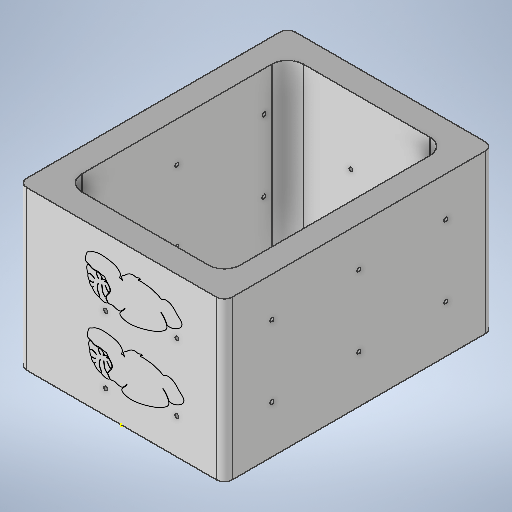
# Autodesk Inventor part: Brain Embedding Chamber 2
Saved by Autodesk Inventor 2025.2 (Build 292293000, 293)
## iProperties
Created: 2020-11-17
Part Number: Brain Embedding Chamber 2
Material: Generic
Document SubType Name: Modeling
Designer: stownsend
Density: 1 g/cm^3
Appearance: Default
Mass: 6.51972 g
Surface Area: 49.5654 cm^2
Volume: 6.51972 cm^3
Author: stownsend
Autodesk Inventor part; units mm, degrees
(part 1 of 2)
ref_plane "YZ Plane" through (0, 0, 0) normal (1, 0, 0) x (0, 1, 0)
ref_plane "XZ Plane" through (0, 0, 0) normal (0, 1, 0) x (-1, 0, 0)
ref_plane "XY Plane" through (0, 0, 0) normal (0, 0, 1) x (1, 0, 0)
sketch "Sketch1" plane through (0, 0, 0) normal (0, 0, 1) x (1, 0, 0)
  line L0 (17, -13) -> (-17, -13)
  line L1 (-17, -13) -> (-17, 13)
  line L2 (-17, 13) -> (17, 13)
  line L3 (17, 13) -> (17, -13)
  line L4 (14, 10) -> (-14, 10)
  line L5 (-14, 10) -> (-14, -10)
  line L6 (-14, -10) -> (14, -10)
  line L7 (14, -10) -> (14, 10)
  point P0 (0, 0)
  dimension "d132" = 26
  dimension "d133" = 34
  dimension "d134" = 17
  dimension "d135" = 13
  dimension "d136" = 20
  dimension "d140" = 28
  dimension "d141" = 14
  dimension "d142" = 10
  constraints: 16 end point, 4 parallel, 2 perpendicular, 1 horizontal, 1 horizontal alignment
  measures "d132" distance between parallel lines of L0 L2
  measures "d133" distance between parallel lines of L1 L3
  measures "d134" distance from line of L3 point (0, 0)
  measures "d135" distance from line of L2 point (0, 0)
  measures "d136" distance between parallel lines of L6 L4
  measures "d140" distance between parallel lines of L5 L7
  measures "d141" distance from line of L7 point (0, 0)
  measures "d142" distance from line of L4 point (0, 0)
extrude "Extrusion1" add sketch "Sketch1" along normal blind 20
sketch "Sketch2" plane through (-14, 0, 0) normal (0, -1, 0) x (1, 0, 0)
  circle A0 centre (3, 15) radius 0.25
  line L0 (31, 20) -> (-3, 20) projected
  circle A1 centre (14, 15) radius 0.25
  circle A2 centre (25, 15) radius 0.25
  circle A3 centre (3, 6) radius 0.25
  circle A4 centre (14, 6) radius 0.25
  circle A5 centre (25, 6) radius 0.25
  point P0 (14, 0)
  point P1 (29, 20)
  dimension "d8" = 0.5
  dimension "d15" = 0.5
  dimension "d18" = 0.5
  dimension "d19" = 0.5
  dimension "d63" = 5
  dimension "d66" = 9
  dimension "d67" = 11
  dimension "d68" = 11
  dimension "d69" = 0.5
  dimension "d70" = 0.5
  constraints: 6 centre point, 4 horizontal alignment, 4 vertical alignment
  measures "d8" diameter of A0
  measures "d15" diameter of A3
  measures "d18" diameter of A4
  measures "d19" diameter of A5
  measures "d63" distance from line of A1.centre L0
  measures "d66" distance of A4.centre A1.centre
  measures "d67" distance of A0.centre A1.centre
  measures "d68" distance of A2.centre A1.centre
  measures "d69" diameter of A1
  measures "d70" diameter of A2
extrude "Extrusion2" cut sketch "Sketch2" along normal through all both and the other way through all
sketch "Sketch3" plane through (0, -12, 0) normal (1, 0, 0) x (0, 0, -1)
  circle A0 centre (-13, 5) radius 0.25
  circle A1 centre (-11.5, 14) radius 0.25
  circle A2 centre (-4.5, 5) radius 0.25
  circle A3 centre (-3, 14) radius 0.25
  point P0 (-20, -1)
  point P1 (0, 12)
  dimension "d28" = 0.5
  dimension "d29" = 0.5
  dimension "d30" = 0.5
  dimension "d31" = 0.5
  dimension "d167" = 7
  dimension "d168" = 2
  dimension "d169" = 9
  constraints: 4 centre point, 2 horizontal alignment
  measures "d28" diameter of A0
  measures "d29" diameter of A1
  measures "d30" diameter of A2
  measures "d31" diameter of A3
  measures "d167" vertical distance of point (0, 12) A2.centre
  measures "d168" vertical distance of point (0, 12) A3.centre
  measures "d169" vertical distance of A3.centre A2.centre
extrude "Extrusion3" cut sketch "Sketch3" along normal through all both and the other way through all
fillet "Fillet1" radius 1 4 edges at (-17, 13, 10) (17, 13, 10) (17, -13, 10) (-17, -13, 10)
fillet "Fillet2" radius 2 4 edges at (-14, 10, 10) (14, 10, 10) (14, -10, 10) (-14, -10, 10)
sketch "Sketch8" plane through (-17, -12, 0) normal (-1, 0, 0) x (0, 0, 1)
  spline S0 degree 3 poles (14.8061, 7.0077) (14.8126, 6.9913) (14.813, 7.0034) (14.8073, 6.9818) knots 0 0 0 0 0.017241 0.017241 0.017241 0.017241
  line L0 (14.8061, 7.0077) -> (14.8126, 6.9913) construction
  line L1 (14.8126, 6.9913) -> (14.813, 7.0034) construction
  line L2 (14.813, 7.0034) -> (14.8073, 6.9818) construction
  line L3 (14.8073, 6.9818) -> (14.7531, 6.8993)
  spline S1 degree 3 poles (14.7531, 6.8993) (14.7531, 6.8993) (14.7198, 6.8577) (14.689, 6.8235) (14.6576, 6.7884) knots 0.034483 0.034483 0.034483 0.034483 0.034483 0.051724 0.051724 0.051724 0.051724
  line L4 (14.7531, 6.8993) -> (14.7198, 6.8577) construction
  line L5 (14.7198, 6.8577) -> (14.689, 6.8235) construction
  line L6 (14.689, 6.8235) -> (14.6576, 6.7884) construction
  spline S2 degree 3 poles (14.6576, 6.7884) (14.6574, 6.7883) (14.497, 6.6092) (14.1688, 6.4006) (13.9416, 6.2976) knots 0.051724 0.051724 0.051724 0.051724 0.051724 0.068966 0.068966 0.068966 0.068966
  line L7 (14.6576, 6.7884) -> (14.497, 6.6092) construction
  line L8 (14.497, 6.6092) -> (14.1688, 6.4006) construction
  line L9 (14.1688, 6.4006) -> (13.9416, 6.2976) construction
  spline S3 degree 3 poles (13.9416, 6.2976) (13.9415, 6.2975) (13.8045, 6.2354) (13.8065, 6.2363) (13.7719, 6.0706) knots 0.068966 0.068966 0.068966 0.068966 0.068966 0.086207 0.086207 0.086207 0.086207
  line L10 (13.9416, 6.2976) -> (13.8045, 6.2354) construction
  line L11 (13.8045, 6.2354) -> (13.8065, 6.2363) construction
  line L12 (13.8065, 6.2363) -> (13.7719, 6.0706) construction
  spline S4 degree 3 poles (13.7719, 6.0706) (13.7719, 6.0705) (13.7476, 5.9537) (13.7493, 5.821) (13.7696, 5.7021) knots 0.086207 0.086207 0.086207 0.086207 0.086207 0.103448 0.103448 0.103448 0.103448
  line L13 (13.7719, 6.0706) -> (13.7476, 5.9537) construction
  line L14 (13.7476, 5.9537) -> (13.7493, 5.821) construction
  line L15 (13.7493, 5.821) -> (13.7696, 5.7021) construction
  spline S5 degree 3 poles (13.7696, 5.7021) (13.7696, 5.7016) (13.8519, 5.2201) (14.3169, 4.3306) (14.8371, 4.3531) knots 0.103448 0.103448 0.103448 0.103448 0.103448 0.12069 0.12069 0.12069 0.12069
  line L16 (13.7696, 5.7021) -> (13.8519, 5.2201) construction
  line L17 (13.8519, 5.2201) -> (14.3169, 4.3306) construction
  line L18 (14.3169, 4.3306) -> (14.8371, 4.3531) construction
  spline S6 degree 3 poles (14.8371, 4.3531) (14.8374, 4.3531) (15.1353, 4.366) (15.3904, 4.7704) (15.6148, 4.9893) knots 0.12069 0.12069 0.12069 0.12069 0.12069 0.137931 0.137931 0.137931 0.137931
  line L19 (14.8371, 4.3531) -> (15.1353, 4.366) construction
  line L20 (15.1353, 4.366) -> (15.3904, 4.7704) construction
  line L21 (15.3904, 4.7704) -> (15.6148, 4.9893) construction
  spline S7 degree 3 poles (15.6148, 4.9893) (15.615, 4.9895) (15.7957, 5.1659) (15.8747, 5.1722) (16.1278, 5.4768) knots 0.137931 0.137931 0.137931 0.137931 0.137931 0.155172 0.155172 0.155172 0.155172
  line L22 (15.6148, 4.9893) -> (15.7957, 5.1659) construction
  line L23 (15.7957, 5.1659) -> (15.8747, 5.1722) construction
  line L24 (15.8747, 5.1722) -> (16.1278, 5.4768) construction
  spline S8 degree 3 poles (16.1278, 5.4768) (16.1279, 5.4769) (16.2353, 5.6061) (16.3693, 5.7817) (16.4219, 5.9929) knots 0.155172 0.155172 0.155172 0.155172 0.155172 0.172414 0.172414 0.172414 0.172414
  line L25 (16.1278, 5.4768) -> (16.2353, 5.6061) construction
  line L26 (16.2353, 5.6061) -> (16.3693, 5.7817) construction
  line L27 (16.3693, 5.7817) -> (16.4219, 5.9929) construction
  spline S9 degree 3 poles (16.4219, 5.9929) (16.422, 5.9936) (16.5964, 6.6941) (16.314, 6.742) (16.2973, 6.9436) knots 0.172414 0.172414 0.172414 0.172414 0.172414 0.189655 0.189655 0.189655 0.189655
  line L28 (16.4219, 5.9929) -> (16.5964, 6.6941) construction
  line L29 (16.5964, 6.6941) -> (16.314, 6.742) construction
  line L30 (16.314, 6.742) -> (16.2973, 6.9436) construction
  spline S10 degree 3 poles (16.2973, 6.9436) (16.2973, 6.9437) (16.2877, 7.0581) (16.3807, 7.1531) (16.4264, 7.2259) knots 0.189655 0.189655 0.189655 0.189655 0.189655 0.206897 0.206897 0.206897 0.206897
  line L31 (16.2973, 6.9436) -> (16.2877, 7.0581) construction
  line L32 (16.2877, 7.0581) -> (16.3807, 7.1531) construction
  line L33 (16.3807, 7.1531) -> (16.4264, 7.2259) construction
  spline S11 degree 3 poles (16.4264, 7.2259) (16.4265, 7.2261) (16.5667, 7.4493) (16.5591, 7.5412) (16.6453, 7.8009) knots 0.206897 0.206897 0.206897 0.206897 0.206897 0.224138 0.224138 0.224138 0.224138
  line L34 (16.4264, 7.2259) -> (16.5667, 7.4493) construction
  line L35 (16.5667, 7.4493) -> (16.5591, 7.5412) construction
  line L36 (16.5591, 7.5412) -> (16.6453, 7.8009) construction
  spline S12 degree 3 poles (16.6453, 7.8009) (16.6454, 7.8012) (16.7199, 8.0256) (16.7906, 8.1594) (16.8362, 8.4188) knots 0.224138 0.224138 0.224138 0.224138 0.224138 0.241379 0.241379 0.241379 0.241379
  line L37 (16.6453, 7.8009) -> (16.7199, 8.0256) construction
  line L38 (16.7199, 8.0256) -> (16.7906, 8.1594) construction
  line L39 (16.7906, 8.1594) -> (16.8362, 8.4188) construction
  spline S13 degree 3 poles (16.8362, 8.4188) (16.8362, 8.4191) (16.8785, 8.6594) (16.8917, 8.9062) (16.9124, 9.1542) knots 0.241379 0.241379 0.241379 0.241379 0.241379 0.258621 0.258621 0.258621 0.258621
  line L40 (16.8362, 8.4188) -> (16.8785, 8.6594) construction
  line L41 (16.8785, 8.6594) -> (16.8917, 8.9062) construction
  line L42 (16.8917, 8.9062) -> (16.9124, 9.1542) construction
  spline S14 degree 3 poles (16.9124, 9.1542) (16.9124, 9.1543) (16.9224, 9.275) (16.9444, 9.4093) (16.9412, 9.5299) knots 0.258621 0.258621 0.258621 0.258621 0.258621 0.275862 0.275862 0.275862 0.275862
  line L43 (16.9124, 9.1542) -> (16.9224, 9.275) construction
  line L44 (16.9224, 9.275) -> (16.9444, 9.4093) construction
  line L45 (16.9444, 9.4093) -> (16.9412, 9.5299) construction
  spline S15 degree 3 poles (16.9412, 9.5299) (16.9412, 9.53) (16.9385, 9.6335) (16.8885, 9.8259) (16.9091, 9.8972) knots 0.275862 0.275862 0.275862 0.275862 0.275862 0.293103 0.293103 0.293103 0.293103
  line L46 (16.9412, 9.5299) -> (16.9385, 9.6335) construction
  line L47 (16.9385, 9.6335) -> (16.8885, 9.8259) construction
  line L48 (16.8885, 9.8259) -> (16.9091, 9.8972) construction
  spline S16 degree 3 poles (16.9091, 9.8972) (16.9092, 9.8971) (17.0279, 9.8719) (17.0313, 9.724) (17.1389, 9.6266) knots 0.293103 0.293103 0.293103 0.293103 0.293103 0.310345 0.310345 0.310345 0.310345
  line L49 (16.9091, 9.8972) -> (17.0279, 9.8719) construction
  line L50 (17.0279, 9.8719) -> (17.0313, 9.724) construction
  line L51 (17.0313, 9.724) -> (17.1389, 9.6266) construction
  spline S17 degree 3 poles (17.1389, 9.6266) (17.139, 9.6267) (17.2834, 9.6997) (17.1799, 9.8422) (17.1328, 9.9522) knots 0.310345 0.310345 0.310345 0.310345 0.310345 0.327586 0.327586 0.327586 0.327586
  line L52 (17.1389, 9.6266) -> (17.2834, 9.6997) construction
  line L53 (17.2834, 9.6997) -> (17.1799, 9.8422) construction
  line L54 (17.1799, 9.8422) -> (17.1328, 9.9522) construction
  spline S18 degree 3 poles (17.1328, 9.9522) (17.1327, 9.9523) (17.0531, 10.138) (17.091, 10.1943) (17.1335, 10.3764) knots 0.327586 0.327586 0.327586 0.327586 0.327586 0.344828 0.344828 0.344828 0.344828
  line L55 (17.1328, 9.9522) -> (17.0531, 10.138) construction
  line L56 (17.0531, 10.138) -> (17.091, 10.1943) construction
  line L57 (17.091, 10.1943) -> (17.1335, 10.3764) construction
  spline S19 degree 3 poles (17.1335, 10.3764) (17.1336, 10.3768) (17.2249, 10.7687) (16.9931, 11.1829) (16.7277, 11.4526) knots 0.344828 0.344828 0.344828 0.344828 0.344828 0.362069 0.362069 0.362069 0.362069
  line L58 (17.1335, 10.3764) -> (17.2249, 10.7687) construction
  line L59 (17.2249, 10.7687) -> (16.9931, 11.1829) construction
  line L60 (16.9931, 11.1829) -> (16.7277, 11.4526) construction
  spline S20 degree 3 poles (16.7277, 11.4526) (16.7276, 11.4528) (16.6041, 11.5783) (16.5961, 11.5866) (16.5019, 11.7347) knots 0.362069 0.362069 0.362069 0.362069 0.362069 0.37931 0.37931 0.37931 0.37931
  line L61 (16.7277, 11.4526) -> (16.6041, 11.5783) construction
  line L62 (16.6041, 11.5783) -> (16.5961, 11.5866) construction
  line L63 (16.5961, 11.5866) -> (16.5019, 11.7347) construction
  spline S21 degree 3 poles (16.5019, 11.7347) (16.5017, 11.7351) (16.2722, 12.0958) (16.2178, 11.9762) (15.8447, 11.8717) knots 0.37931 0.37931 0.37931 0.37931 0.37931 0.396552 0.396552 0.396552 0.396552
  line L64 (16.5019, 11.7347) -> (16.2722, 12.0958) construction
  line L65 (16.2722, 12.0958) -> (16.2178, 11.9762) construction
  line L66 (16.2178, 11.9762) -> (15.8447, 11.8717) construction
  spline S22 degree 3 poles (15.8447, 11.8717) (15.8447, 11.8717) (15.8613, 11.8841) (15.9767, 12.0055) (15.9897, 12.0289) knots 0.396552 0.396552 0.396552 0.396552 0.396552 0.413793 0.413793 0.413793 0.413793
  line L67 (15.8447, 11.8717) -> (15.8613, 11.8841) construction
  line L68 (15.8613, 11.8841) -> (15.9767, 12.0055) construction
  line L69 (15.9767, 12.0055) -> (15.9897, 12.0289) construction
  spline S23 degree 3 poles (15.9897, 12.0289) (15.9897, 12.029) (16.0358, 12.1116) (15.9868, 12.1947) (15.9691, 12.2712) knots 0.413793 0.413793 0.413793 0.413793 0.413793 0.431034 0.431034 0.431034 0.431034
  line L70 (15.9897, 12.0289) -> (16.0358, 12.1116) construction
  line L71 (16.0358, 12.1116) -> (15.9868, 12.1947) construction
  line L72 (15.9868, 12.1947) -> (15.9691, 12.2712) construction
  spline S24 degree 3 poles (15.9691, 12.2712) (15.9694, 12.271) (16.298, 12.106) (16.521, 12.0677) (16.7612, 12.3366) knots 0.431034 0.431034 0.431034 0.431034 0.431034 0.448276 0.448276 0.448276 0.448276
  line L73 (15.9691, 12.2712) -> (16.298, 12.106) construction
  line L74 (16.298, 12.106) -> (16.521, 12.0677) construction
  line L75 (16.521, 12.0677) -> (16.7612, 12.3366) construction
  spline S25 degree 3 poles (16.7612, 12.3366) (16.7614, 12.3368) (16.9635, 12.5631) (17.0591, 12.6843) (17.1585, 13.067) knots 0.448276 0.448276 0.448276 0.448276 0.448276 0.465517 0.465517 0.465517 0.465517
  line L76 (16.7612, 12.3366) -> (16.9635, 12.5631) construction
  line L77 (16.9635, 12.5631) -> (17.0591, 12.6843) construction
  line L78 (17.0591, 12.6843) -> (17.1585, 13.067) construction
  spline S26 degree 3 poles (17.1585, 13.067) (17.1587, 13.0675) (17.2966, 13.5982) (17.4342, 14.5011) (17.3195, 15.0596) knots 0.465517 0.465517 0.465517 0.465517 0.465517 0.482759 0.482759 0.482759 0.482759
  line L79 (17.1585, 13.067) -> (17.2966, 13.5982) construction
  line L80 (17.2966, 13.5982) -> (17.4342, 14.5011) construction
  line L81 (17.4342, 14.5011) -> (17.3195, 15.0596) construction
  spline S27 degree 3 poles (17.3195, 15.0596) (17.3193, 15.0604) (17.1617, 15.8281) (17.1237, 15.5942) (16.8389, 16.2465) knots 0.482759 0.482759 0.482759 0.482759 0.482759 0.5 0.5 0.5 0.5
  line L82 (17.3195, 15.0596) -> (17.1617, 15.8281) construction
  line L83 (17.1617, 15.8281) -> (17.1237, 15.5942) construction
  line L84 (17.1237, 15.5942) -> (16.8389, 16.2465) construction
  spline S28 degree 3 poles (16.8389, 16.2465) (16.8388, 16.2467) (16.7576, 16.4327) (16.2269, 16.5214) (16.0324, 16.566) knots 0.5 0.5 0.5 0.5 0.5 0.517241 0.517241 0.517241 0.517241
  line L85 (16.8389, 16.2465) -> (16.7576, 16.4327) construction
  line L86 (16.7576, 16.4327) -> (16.2269, 16.5214) construction
  line L87 (16.2269, 16.5214) -> (16.0324, 16.566) construction
  spline S29 degree 3 poles (16.0324, 16.566) (16.032, 16.5661) (15.596, 16.666) (15.6174, 16.2933) (15.4954, 16.0148) knots 0.517241 0.517241 0.517241 0.517241 0.517241 0.534483 0.534483 0.534483 0.534483
  line L88 (16.0324, 16.566) -> (15.596, 16.666) construction
  line L89 (15.596, 16.666) -> (15.6174, 16.2933) construction
  line L90 (15.6174, 16.2933) -> (15.4954, 16.0148) construction
  spline S30 degree 3 poles (15.4954, 16.0148) (15.4953, 16.0147) (15.4402, 15.8888) (15.3306, 15.7816) (15.3055, 15.635) knots 0.534483 0.534483 0.534483 0.534483 0.534483 0.551724 0.551724 0.551724 0.551724
  line L91 (15.4954, 16.0148) -> (15.4402, 15.8888) construction
  line L92 (15.4402, 15.8888) -> (15.3306, 15.7816) construction
  line L93 (15.3306, 15.7816) -> (15.3055, 15.635) construction
  spline S31 degree 3 poles (15.3055, 15.635) (15.3055, 15.6349) (15.2801, 15.4867) (15.3168, 15.2693) (15.3266, 15.1182) knots 0.551724 0.551724 0.551724 0.551724 0.551724 0.568966 0.568966 0.568966 0.568966
  line L94 (15.3055, 15.635) -> (15.2801, 15.4867) construction
  line L95 (15.2801, 15.4867) -> (15.3168, 15.2693) construction
  line L96 (15.3168, 15.2693) -> (15.3266, 15.1182) construction
  spline S32 degree 3 poles (15.3266, 15.1182) (15.3266, 15.118) (15.3408, 14.8989) (15.2718, 14.8507) (15.226, 14.6656) knots 0.568966 0.568966 0.568966 0.568966 0.568966 0.586207 0.586207 0.586207 0.586207
  line L97 (15.3266, 15.1182) -> (15.3408, 14.8989) construction
  line L98 (15.3408, 14.8989) -> (15.2718, 14.8507) construction
  line L99 (15.2718, 14.8507) -> (15.226, 14.6656) construction
  spline S33 degree 3 poles (15.226, 14.6656) (15.2259, 14.6655) (15.1901, 14.5208) (15.198, 14.2448) (15.1702, 14.1657) knots 0.586207 0.586207 0.586207 0.586207 0.586207 0.603448 0.603448 0.603448 0.603448
  line L100 (15.226, 14.6656) -> (15.1901, 14.5208) construction
  line L101 (15.1901, 14.5208) -> (15.198, 14.2448) construction
  line L102 (15.198, 14.2448) -> (15.1702, 14.1657) construction
  spline S34 degree 3 poles (15.1702, 14.1657) (15.1701, 14.1656) (15.1401, 14.0803) (14.9265, 13.9924) (14.84, 13.9243) knots 0.603448 0.603448 0.603448 0.603448 0.603448 0.62069 0.62069 0.62069 0.62069
  line L103 (15.1702, 14.1657) -> (15.1401, 14.0803) construction
  line L104 (15.1401, 14.0803) -> (14.9265, 13.9924) construction
  line L105 (14.9265, 13.9924) -> (14.84, 13.9243) construction
  spline S35 degree 3 poles (14.84, 13.9243) (14.8398, 13.9241) (14.5692, 13.7109) (14.5143, 13.5521) (14.212, 13.4414) knots 0.62069 0.62069 0.62069 0.62069 0.62069 0.637931 0.637931 0.637931 0.637931
  line L106 (14.84, 13.9243) -> (14.5692, 13.7109) construction
  line L107 (14.5692, 13.7109) -> (14.5143, 13.5521) construction
  line L108 (14.5143, 13.5521) -> (14.212, 13.4414) construction
  spline S36 degree 3 poles (14.212, 13.4414) (14.2116, 13.4412) (13.847, 13.3077) (13.6081, 13.5837) (13.4333, 13.7142) knots 0.637931 0.637931 0.637931 0.637931 0.637931 0.655172 0.655172 0.655172 0.655172
  line L109 (14.212, 13.4414) -> (13.847, 13.3077) construction
  line L110 (13.847, 13.3077) -> (13.6081, 13.5837) construction
  line L111 (13.6081, 13.5837) -> (13.4333, 13.7142) construction
  spline S37 degree 3 poles (13.4333, 13.7142) (13.4329, 13.7145) (13.0095, 14.0307) (12.9457, 13.9631) (12.6948, 13.7991) knots 0.655172 0.655172 0.655172 0.655172 0.655172 0.672414 0.672414 0.672414 0.672414
  line L112 (13.4333, 13.7142) -> (13.0095, 14.0307) construction
  line L113 (13.0095, 14.0307) -> (12.9457, 13.9631) construction
  line L114 (12.9457, 13.9631) -> (12.6948, 13.7991) construction
  spline S38 degree 3 poles (12.6948, 13.7991) (12.6946, 13.799) (12.5373, 13.6961) (12.4745, 13.7226) (12.4908, 13.4539) knots 0.672414 0.672414 0.672414 0.672414 0.672414 0.689655 0.689655 0.689655 0.689655
  line L115 (12.6948, 13.7991) -> (12.5373, 13.6961) construction
  line L116 (12.5373, 13.6961) -> (12.4745, 13.7226) construction
  line L117 (12.4745, 13.7226) -> (12.4908, 13.4539) construction
  spline S39 degree 3 poles (12.4908, 13.4539) (12.4908, 13.4537) (12.5019, 13.2712) (12.5956, 13.174) (12.5115, 12.9833) knots 0.689655 0.689655 0.689655 0.689655 0.689655 0.706897 0.706897 0.706897 0.706897
  line L118 (12.4908, 13.4539) -> (12.5019, 13.2712) construction
  line L119 (12.5019, 13.2712) -> (12.5956, 13.174) construction
  line L120 (12.5956, 13.174) -> (12.5115, 12.9833) construction
  spline S40 degree 3 poles (12.5115, 12.9833) (12.5113, 12.983) (12.3979, 12.7261) (12.2511, 12.3791) (12.4367, 12.0826) knots 0.706897 0.706897 0.706897 0.706897 0.706897 0.724138 0.724138 0.724138 0.724138
  line L121 (12.5115, 12.9833) -> (12.3979, 12.7261) construction
  line L122 (12.3979, 12.7261) -> (12.2511, 12.3791) construction
  line L123 (12.2511, 12.3791) -> (12.4367, 12.0826) construction
  spline S41 degree 3 poles (12.4367, 12.0826) (12.4368, 12.0825) (12.4996, 11.9821) (12.6265, 11.8765) (12.7109, 11.8012) knots 0.724138 0.724138 0.724138 0.724138 0.724138 0.741379 0.741379 0.741379 0.741379
  line L124 (12.4367, 12.0826) -> (12.4996, 11.9821) construction
  line L125 (12.4996, 11.9821) -> (12.6265, 11.8765) construction
  line L126 (12.6265, 11.8765) -> (12.7109, 11.8012) construction
  spline S42 degree 3 poles (12.7109, 11.8012) (12.7109, 11.8012) (12.7532, 11.7635) (12.8205, 11.7124) (12.8733, 11.6779) knots 0.741379 0.741379 0.741379 0.741379 0.741379 0.758621 0.758621 0.758621 0.758621
  line L127 (12.7109, 11.8012) -> (12.7532, 11.7635) construction
  line L128 (12.7532, 11.7635) -> (12.8205, 11.7124) construction
  line L129 (12.8205, 11.7124) -> (12.8733, 11.6779) construction
  spline S43 degree 3 poles (12.8733, 11.6779) (12.8734, 11.6778) (13.0031, 11.5931) (13.0298, 11.6134) (13.0171, 11.557) knots 0.758621 0.758621 0.758621 0.758621 0.758621 0.775862 0.775862 0.775862 0.775862
  line L130 (12.8733, 11.6779) -> (13.0031, 11.5931) construction
  line L131 (13.0031, 11.5931) -> (13.0298, 11.6134) construction
  line L132 (13.0298, 11.6134) -> (13.0171, 11.557) construction
  spline S44 degree 3 poles (13.0171, 11.557) (13.0171, 11.557) (13.014, 11.5564) (13.0055, 11.5565) (13.0075, 11.5566) knots 0.775862 0.775862 0.775862 0.775862 0.775862 0.793103 0.793103 0.793103 0.793103
  line L133 (13.0171, 11.557) -> (13.014, 11.5564) construction
  line L134 (13.014, 11.5564) -> (13.0055, 11.5565) construction
  line L135 (13.0055, 11.5565) -> (13.0075, 11.5566) construction
  line L136 (13.0075, 11.5566) -> (12.9679, 11.5649)
  spline S45 degree 3 poles (12.9679, 11.5649) (12.9676, 11.565) (12.676, 11.6892) (12.365, 12.1397) (12.1726, 12.1992) knots 0.810345 0.810345 0.810345 0.810345 0.810345 0.827586 0.827586 0.827586 0.827586
  line L137 (12.9679, 11.5649) -> (12.676, 11.6892) construction
  line L138 (12.676, 11.6892) -> (12.365, 12.1397) construction
  line L139 (12.365, 12.1397) -> (12.1726, 12.1992) construction
  spline S46 degree 3 poles (12.1726, 12.1992) (12.1723, 12.1994) (11.8022, 12.3138) (11.6485, 11.6062) (11.6148, 11.2762) knots 0.827586 0.827586 0.827586 0.827586 0.827586 0.844828 0.844828 0.844828 0.844828
  line L140 (12.1726, 12.1992) -> (11.8022, 12.3138) construction
  line L141 (11.8022, 12.3138) -> (11.6485, 11.6062) construction
  line L142 (11.6485, 11.6062) -> (11.6148, 11.2762) construction
  spline S47 degree 3 poles (11.6148, 11.2762) (11.6147, 11.2754) (11.5349, 10.4935) (11.8052, 9.4632) (12.0383, 8.7151) knots 0.844828 0.844828 0.844828 0.844828 0.844828 0.862069 0.862069 0.862069 0.862069
  line L143 (11.6148, 11.2762) -> (11.5349, 10.4935) construction
  line L144 (11.5349, 10.4935) -> (11.8052, 9.4632) construction
  line L145 (11.8052, 9.4632) -> (12.0383, 8.7151) construction
  spline S48 degree 3 poles (12.0383, 8.7151) (12.0386, 8.7143) (12.2932, 7.8968) (12.546, 7.2313) (12.9917, 6.6526) knots 0.862069 0.862069 0.862069 0.862069 0.862069 0.87931 0.87931 0.87931 0.87931
  line L146 (12.0383, 8.7151) -> (12.2932, 7.8968) construction
  line L147 (12.2932, 7.8968) -> (12.546, 7.2313) construction
  line L148 (12.546, 7.2313) -> (12.9917, 6.6526) construction
  spline S49 degree 3 poles (12.9917, 6.6526) (12.9919, 6.6523) (13.2189, 6.3577) (13.4659, 6.1033) (13.9717, 6.3634) knots 0.87931 0.87931 0.87931 0.87931 0.87931 0.896552 0.896552 0.896552 0.896552
  line L149 (12.9917, 6.6526) -> (13.2189, 6.3577) construction
  line L150 (13.2189, 6.3577) -> (13.4659, 6.1033) construction
  line L151 (13.4659, 6.1033) -> (13.9717, 6.3634) construction
  spline S50 degree 3 poles (13.9717, 6.3634) (13.9718, 6.3635) (14.1213, 6.4404) (14.4318, 6.6258) (14.5363, 6.735) knots 0.896552 0.896552 0.896552 0.896552 0.896552 0.913793 0.913793 0.913793 0.913793
  line L152 (13.9717, 6.3634) -> (14.1213, 6.4404) construction
  line L153 (14.1213, 6.4404) -> (14.4318, 6.6258) construction
  line L154 (14.4318, 6.6258) -> (14.5363, 6.735) construction
  spline S51 degree 3 poles (14.5363, 6.735) (14.5363, 6.735) (14.5727, 6.7731) (14.5942, 6.7956) (14.6299, 6.8322) knots 0.913793 0.913793 0.913793 0.913793 0.913793 0.931034 0.931034 0.931034 0.931034
  line L155 (14.5363, 6.735) -> (14.5727, 6.7731) construction
  line L156 (14.5727, 6.7731) -> (14.5942, 6.7956) construction
  line L157 (14.5942, 6.7956) -> (14.6299, 6.8322) construction
  spline S52 degree 3 poles (14.6299, 6.8322) (14.63, 6.8322) (14.6725, 6.8758) (14.6861, 6.8894) (14.719, 6.9336) knots 0.931034 0.931034 0.931034 0.931034 0.931034 0.948276 0.948276 0.948276 0.948276
  line L158 (14.6299, 6.8322) -> (14.6725, 6.8758) construction
  line L159 (14.6725, 6.8758) -> (14.6861, 6.8894) construction
  line L160 (14.6861, 6.8894) -> (14.719, 6.9336) construction
  spline S53 degree 3 poles (14.719, 6.9336) (14.719, 6.9336) (14.7334, 6.9531) (14.7503, 6.9789) (14.76, 6.9891) knots 0.948276 0.948276 0.948276 0.948276 0.948276 0.965517 0.965517 0.965517 0.965517
  line L161 (14.719, 6.9336) -> (14.7334, 6.9531) construction
  line L162 (14.7334, 6.9531) -> (14.7503, 6.9789) construction
  line L163 (14.7503, 6.9789) -> (14.76, 6.9891) construction
  spline S54 degree 3 poles (14.76, 6.9891) (14.7601, 6.9892) (14.7996, 7.0307) (14.752, 7.0291) (14.8061, 7.0077) knots 0.965517 0.965517 0.965517 0.965517 0.965517 1 1 1 1
  line L164 (14.76, 6.9891) -> (14.7996, 7.0307) construction
  line L165 (14.7996, 7.0307) -> (14.752, 7.0291) construction
  line L166 (14.752, 7.0291) -> (14.8061, 7.0077) construction
  spline S55 degree 3 poles (12.4974, 13.7521) (12.6419, 13.7918) (12.7467, 13.9079) (12.8771, 13.9659) knots 0 0 0 0 0.019231 0.019231 0.019231 0.019231
  line L167 (12.4974, 13.7521) -> (12.6419, 13.7918) construction
  line L168 (12.6419, 13.7918) -> (12.7467, 13.9079) construction
  line L169 (12.7467, 13.9079) -> (12.8771, 13.9659) construction
  spline S56 degree 3 poles (12.8771, 13.9659) (12.8772, 13.966) (13.0067, 14.0236) (12.9336, 13.9576) (13.0374, 14.1075) knots 0.019231 0.019231 0.019231 0.019231 0.019231 0.038462 0.038462 0.038462 0.038462
  line L170 (12.8771, 13.9659) -> (13.0067, 14.0236) construction
  line L171 (13.0067, 14.0236) -> (12.9336, 13.9576) construction
  line L172 (12.9336, 13.9576) -> (13.0374, 14.1075) construction
  spline S57 degree 3 poles (13.0374, 14.1075) (13.0375, 14.1076) (13.0801, 14.1692) (13.1267, 14.2293) (13.1746, 14.2723) knots 0.038462 0.038462 0.038462 0.038462 0.038462 0.057692 0.057692 0.057692 0.057692
  line L173 (13.0374, 14.1075) -> (13.0801, 14.1692) construction
  line L174 (13.0801, 14.1692) -> (13.1267, 14.2293) construction
  line L175 (13.1267, 14.2293) -> (13.1746, 14.2723) construction
  spline S58 degree 3 poles (13.1746, 14.2723) (13.1747, 14.2724) (13.2997, 14.3845) (13.401, 14.4052) (13.6073, 14.4417) knots 0.057692 0.057692 0.057692 0.057692 0.057692 0.076923 0.076923 0.076923 0.076923
  line L176 (13.1746, 14.2723) -> (13.2997, 14.3845) construction
  line L177 (13.2997, 14.3845) -> (13.401, 14.4052) construction
  line L178 (13.401, 14.4052) -> (13.6073, 14.4417) construction
  spline S59 degree 3 poles (13.6073, 14.4417) (13.6074, 14.4417) (13.7075, 14.4595) (14.0537, 14.5252) (14.13, 14.4829) knots 0.076923 0.076923 0.076923 0.076923 0.076923 0.096154 0.096154 0.096154 0.096154
  line L179 (13.6073, 14.4417) -> (13.7075, 14.4595) construction
  line L180 (13.7075, 14.4595) -> (14.0537, 14.5252) construction
  line L181 (14.0537, 14.5252) -> (14.13, 14.4829) construction
  spline S60 degree 3 poles (14.13, 14.4829) (14.13, 14.4829) (14.0581, 14.4159) (13.4193, 14.4743) (13.1787, 14.2362) knots 0.096154 0.096154 0.096154 0.096154 0.096154 0.115385 0.115385 0.115385 0.115385
  line L182 (14.13, 14.4829) -> (14.0581, 14.4159) construction
  line L183 (14.0581, 14.4159) -> (13.4193, 14.4743) construction
  line L184 (13.4193, 14.4743) -> (13.1787, 14.2362) construction
  spline S61 degree 3 poles (13.1787, 14.2362) (13.1786, 14.2362) (13.1356, 14.1936) (13.0336, 14.0617) (13.0047, 13.9849) knots 0.115385 0.115385 0.115385 0.115385 0.115385 0.134615 0.134615 0.134615 0.134615
  line L185 (13.1787, 14.2362) -> (13.1356, 14.1936) construction
  line L186 (13.1356, 14.1936) -> (13.0336, 14.0617) construction
  line L187 (13.0336, 14.0617) -> (13.0047, 13.9849) construction
  spline S62 degree 3 poles (13.0047, 13.9849) (13.0048, 13.9849) (13.1544, 13.9593) (13.358, 13.832) (13.4766, 13.7415) knots 0.134615 0.134615 0.134615 0.134615 0.134615 0.153846 0.153846 0.153846 0.153846
  line L188 (13.0047, 13.9849) -> (13.1544, 13.9593) construction
  line L189 (13.1544, 13.9593) -> (13.358, 13.832) construction
  line L190 (13.358, 13.832) -> (13.4766, 13.7415) construction
  spline S63 degree 3 poles (13.4766, 13.7415) (13.4766, 13.7414) (13.532, 13.6992) (13.5546, 13.6715) (13.6147, 13.6325) knots 0.153846 0.153846 0.153846 0.153846 0.153846 0.173077 0.173077 0.173077 0.173077
  line L191 (13.4766, 13.7415) -> (13.532, 13.6992) construction
  line L192 (13.532, 13.6992) -> (13.5546, 13.6715) construction
  line L193 (13.5546, 13.6715) -> (13.6147, 13.6325) construction
  spline S64 degree 3 poles (13.6147, 13.6325) (13.6147, 13.6325) (13.6926, 13.6503) (13.7417, 13.6879) (13.7802, 13.7299) knots 0.173077 0.173077 0.173077 0.173077 0.173077 0.192308 0.192308 0.192308 0.192308
  line L194 (13.6147, 13.6325) -> (13.6926, 13.6503) construction
  line L195 (13.6926, 13.6503) -> (13.7417, 13.6879) construction
  line L196 (13.7417, 13.6879) -> (13.7802, 13.7299) construction
  spline S65 degree 3 poles (13.7802, 13.7299) (13.7805, 13.7302) (14.0747, 14.0504) (13.9714, 13.8769) (14.1593, 14.0176) knots 0.192308 0.192308 0.192308 0.192308 0.192308 0.211538 0.211538 0.211538 0.211538
  line L197 (13.7802, 13.7299) -> (14.0747, 14.0504) construction
  line L198 (14.0747, 14.0504) -> (13.9714, 13.8769) construction
  line L199 (13.9714, 13.8769) -> (14.1593, 14.0176) construction
  spline S66 degree 3 poles (14.1593, 14.0176) (14.1594, 14.0176) (14.2183, 14.0617) (14.1798, 14.0607) (14.2522, 14.076) knots 0.211538 0.211538 0.211538 0.211538 0.211538 0.230769 0.230769 0.230769 0.230769
  line L200 (14.1593, 14.0176) -> (14.2183, 14.0617) construction
  line L201 (14.2183, 14.0617) -> (14.1798, 14.0607) construction
  line L202 (14.1798, 14.0607) -> (14.2522, 14.076) construction
  spline S67 degree 3 poles (14.2522, 14.076) (14.2521, 14.0759) (14.2038, 13.9594) (14.0488, 13.9517) (13.9389, 13.8573) knots 0.230769 0.230769 0.230769 0.230769 0.230769 0.25 0.25 0.25 0.25
  line L203 (14.2522, 14.076) -> (14.2038, 13.9594) construction
  line L204 (14.2038, 13.9594) -> (14.0488, 13.9517) construction
  line L205 (14.0488, 13.9517) -> (13.9389, 13.8573) construction
  spline S68 degree 3 poles (13.9389, 13.8573) (13.9388, 13.8572) (13.8334, 13.7667) (13.8061, 13.6697) (13.6479, 13.6067) knots 0.25 0.25 0.25 0.25 0.25 0.269231 0.269231 0.269231 0.269231
  line L206 (13.9389, 13.8573) -> (13.8334, 13.7667) construction
  line L207 (13.8334, 13.7667) -> (13.8061, 13.6697) construction
  line L208 (13.8061, 13.6697) -> (13.6479, 13.6067) construction
  spline S69 degree 3 poles (13.6479, 13.6067) (13.6481, 13.6065) (13.8452, 13.422) (14.0818, 13.4112) (14.336, 13.5548) knots 0.269231 0.269231 0.269231 0.269231 0.269231 0.288462 0.288462 0.288462 0.288462
  line L209 (13.6479, 13.6067) -> (13.8452, 13.422) construction
  line L210 (13.8452, 13.422) -> (14.0818, 13.4112) construction
  line L211 (14.0818, 13.4112) -> (14.336, 13.5548) construction
  spline S70 degree 3 poles (14.336, 13.5548) (14.3361, 13.5549) (14.4636, 13.6269) (14.5064, 13.6777) (14.5983, 13.7694) knots 0.288462 0.288462 0.288462 0.288462 0.288462 0.307692 0.307692 0.307692 0.307692
  line L212 (14.336, 13.5548) -> (14.4636, 13.6269) construction
  line L213 (14.4636, 13.6269) -> (14.5064, 13.6777) construction
  line L214 (14.5064, 13.6777) -> (14.5983, 13.7694) construction
  spline S71 degree 3 poles (14.5983, 13.7694) (14.5985, 13.7695) (14.7532, 13.9239) (14.6177, 13.9966) (14.6258, 14.1174) knots 0.307692 0.307692 0.307692 0.307692 0.307692 0.326923 0.326923 0.326923 0.326923
  line L215 (14.5983, 13.7694) -> (14.7532, 13.9239) construction
  line L216 (14.7532, 13.9239) -> (14.6177, 13.9966) construction
  line L217 (14.6177, 13.9966) -> (14.6258, 14.1174) construction
  line L218 (14.6258, 14.1174) -> (14.6307, 14.1398)
  spline S72 degree 3 poles (14.6307, 14.1398) (14.6307, 14.1397) (14.6719, 14.0883) (14.6981, 13.9681) (14.7018, 13.8998) knots 0.346154 0.346154 0.346154 0.346154 0.346154 0.365385 0.365385 0.365385 0.365385
  line L219 (14.6307, 14.1398) -> (14.6719, 14.0883) construction
  line L220 (14.6719, 14.0883) -> (14.6981, 13.9681) construction
  line L221 (14.6981, 13.9681) -> (14.7018, 13.8998) construction
  spline S73 degree 3 poles (14.7018, 13.8998) (14.7021, 13.9001) (14.9382, 14.1626) (14.8001, 14.2693) (14.7578, 14.3559) knots 0.365385 0.365385 0.365385 0.365385 0.365385 0.384615 0.384615 0.384615 0.384615
  line L222 (14.7018, 13.8998) -> (14.9382, 14.1626) construction
  line L223 (14.9382, 14.1626) -> (14.8001, 14.2693) construction
  line L224 (14.8001, 14.2693) -> (14.7578, 14.3559) construction
  spline S74 degree 3 poles (14.7578, 14.3559) (14.7579, 14.356) (14.8587, 14.4327) (14.9144, 14.4388) (14.9933, 14.5294) knots 0.384615 0.384615 0.384615 0.384615 0.384615 0.403846 0.403846 0.403846 0.403846
  line L225 (14.7578, 14.3559) -> (14.8587, 14.4327) construction
  line L226 (14.8587, 14.4327) -> (14.9144, 14.4388) construction
  line L227 (14.9144, 14.4388) -> (14.9933, 14.5294) construction
  spline S75 degree 3 poles (14.9933, 14.5294) (14.9932, 14.5294) (14.8839, 14.5312) (14.7408, 14.5118) (14.6488, 14.5623) knots 0.403846 0.403846 0.403846 0.403846 0.403846 0.423077 0.423077 0.423077 0.423077
  line L228 (14.9933, 14.5294) -> (14.8839, 14.5312) construction
  line L229 (14.8839, 14.5312) -> (14.7408, 14.5118) construction
  line L230 (14.7408, 14.5118) -> (14.6488, 14.5623) construction
  spline S76 degree 3 poles (14.6488, 14.5623) (14.6488, 14.5623) (14.677, 14.5852) (14.6741, 14.5791) (14.7588, 14.5675) knots 0.423077 0.423077 0.423077 0.423077 0.423077 0.442308 0.442308 0.442308 0.442308
  line L231 (14.6488, 14.5623) -> (14.677, 14.5852) construction
  line L232 (14.677, 14.5852) -> (14.6741, 14.5791) construction
  line L233 (14.6741, 14.5791) -> (14.7588, 14.5675) construction
  spline S77 degree 3 poles (14.7588, 14.5675) (14.759, 14.5675) (14.9682, 14.539) (15.0405, 14.5546) (15.1217, 14.6747) knots 0.442308 0.442308 0.442308 0.442308 0.442308 0.461538 0.461538 0.461538 0.461538
  line L234 (14.7588, 14.5675) -> (14.9682, 14.539) construction
  line L235 (14.9682, 14.539) -> (15.0405, 14.5546) construction
  line L236 (15.0405, 14.5546) -> (15.1217, 14.6747) construction
  spline S78 degree 3 poles (15.1217, 14.6747) (15.1218, 14.6749) (15.2251, 14.8279) (15.4067, 15.3496) (14.8113, 15.0645) knots 0.461538 0.461538 0.461538 0.461538 0.461538 0.480769 0.480769 0.480769 0.480769
  line L237 (15.1217, 14.6747) -> (15.2251, 14.8279) construction
  line L238 (15.2251, 14.8279) -> (15.4067, 15.3496) construction
  line L239 (15.4067, 15.3496) -> (14.8113, 15.0645) construction
  spline S79 degree 3 poles (14.8113, 15.0645) (14.8111, 15.0644) (14.6242, 14.975) (14.6532, 14.8811) (14.5749, 14.8718) knots 0.480769 0.480769 0.480769 0.480769 0.480769 0.5 0.5 0.5 0.5
  line L240 (14.8113, 15.0645) -> (14.6242, 14.975) construction
  line L241 (14.6242, 14.975) -> (14.6532, 14.8811) construction
  line L242 (14.6532, 14.8811) -> (14.5749, 14.8718) construction
  spline S80 degree 3 poles (14.5749, 14.8718) (14.5749, 14.8719) (14.5835, 14.9351) (14.7168, 15.0554) (14.7856, 15.0894) knots 0.5 0.5 0.5 0.5 0.5 0.519231 0.519231 0.519231 0.519231
  line L243 (14.5749, 14.8718) -> (14.5835, 14.9351) construction
  line L244 (14.5835, 14.9351) -> (14.7168, 15.0554) construction
  line L245 (14.7168, 15.0554) -> (14.7856, 15.0894) construction
  spline S81 degree 3 poles (14.7856, 15.0894) (14.7857, 15.0895) (14.9095, 15.1506) (14.9866, 15.1641) (15.1376, 15.1839) knots 0.519231 0.519231 0.519231 0.519231 0.519231 0.538462 0.538462 0.538462 0.538462
  line L246 (14.7856, 15.0894) -> (14.9095, 15.1506) construction
  line L247 (14.9095, 15.1506) -> (14.9866, 15.1641) construction
  line L248 (14.9866, 15.1641) -> (15.1376, 15.1839) construction
  spline S82 degree 3 poles (15.1376, 15.1839) (15.1379, 15.184) (15.3879, 15.2169) (15.1196, 15.4877) (15.3575, 15.8672) knots 0.538462 0.538462 0.538462 0.538462 0.538462 0.557692 0.557692 0.557692 0.557692
  line L249 (15.1376, 15.1839) -> (15.3879, 15.2169) construction
  line L250 (15.3879, 15.2169) -> (15.1196, 15.4877) construction
  line L251 (15.1196, 15.4877) -> (15.3575, 15.8672) construction
  spline S83 degree 3 poles (15.3575, 15.8672) (15.3576, 15.8673) (15.3965, 15.9293) (15.4964, 16.08) (15.475, 16.1688) knots 0.557692 0.557692 0.557692 0.557692 0.557692 0.576923 0.576923 0.576923 0.576923
  line L252 (15.3575, 15.8672) -> (15.3965, 15.9293) construction
  line L253 (15.3965, 15.9293) -> (15.4964, 16.08) construction
  line L254 (15.4964, 16.08) -> (15.475, 16.1688) construction
  spline S84 degree 3 poles (15.475, 16.1688) (15.4749, 16.1692) (15.3831, 16.5492) (14.594, 16.3515) (14.478, 16.245) knots 0.576923 0.576923 0.576923 0.576923 0.576923 0.596154 0.596154 0.596154 0.596154
  line L255 (15.475, 16.1688) -> (15.3831, 16.5492) construction
  line L256 (15.3831, 16.5492) -> (14.594, 16.3515) construction
  line L257 (14.594, 16.3515) -> (14.478, 16.245) construction
  spline S85 degree 3 poles (14.478, 16.245) (14.4781, 16.2449) (14.5715, 16.1148) (14.6335, 16.0311) (14.5737, 15.8095) knots 0.596154 0.596154 0.596154 0.596154 0.596154 0.615385 0.615385 0.615385 0.615385
  line L258 (14.478, 16.245) -> (14.5715, 16.1148) construction
  line L259 (14.5715, 16.1148) -> (14.6335, 16.0311) construction
  line L260 (14.6335, 16.0311) -> (14.5737, 15.8095) construction
  spline S86 degree 3 poles (14.5737, 15.8095) (14.5736, 15.8093) (14.5346, 15.6649) (14.4478, 15.4773) (14.3392, 15.4293) knots 0.615385 0.615385 0.615385 0.615385 0.615385 0.634615 0.634615 0.634615 0.634615
  line L261 (14.5737, 15.8095) -> (14.5346, 15.6649) construction
  line L262 (14.5346, 15.6649) -> (14.4478, 15.4773) construction
  line L263 (14.4478, 15.4773) -> (14.3392, 15.4293) construction
  spline S87 degree 3 poles (14.3392, 15.4293) (14.3393, 15.4293) (14.3583, 15.4775) (14.6904, 15.8487) (14.5178, 16.1322) knots 0.634615 0.634615 0.634615 0.634615 0.634615 0.653846 0.653846 0.653846 0.653846
  line L264 (14.3392, 15.4293) -> (14.3583, 15.4775) construction
  line L265 (14.3583, 15.4775) -> (14.6904, 15.8487) construction
  line L266 (14.6904, 15.8487) -> (14.5178, 16.1322) construction
  spline S88 degree 3 poles (14.5178, 16.1322) (14.5177, 16.1323) (14.4418, 16.2569) (14.3624, 16.2761) (14.1414, 16.2403) knots 0.653846 0.653846 0.653846 0.653846 0.653846 0.673077 0.673077 0.673077 0.673077
  line L267 (14.5178, 16.1322) -> (14.4418, 16.2569) construction
  line L268 (14.4418, 16.2569) -> (14.3624, 16.2761) construction
  line L269 (14.3624, 16.2761) -> (14.1414, 16.2403) construction
  spline S89 degree 3 poles (14.1414, 16.2403) (14.1412, 16.2402) (13.9587, 16.2106) (13.917, 16.132) (13.7998, 16.0897) knots 0.673077 0.673077 0.673077 0.673077 0.673077 0.692308 0.692308 0.692308 0.692308
  line L270 (14.1414, 16.2403) -> (13.9587, 16.2106) construction
  line L271 (13.9587, 16.2106) -> (13.917, 16.132) construction
  line L272 (13.917, 16.132) -> (13.7998, 16.0897) construction
  spline S90 degree 3 poles (13.7998, 16.0897) (13.7998, 16.0896) (13.8193, 15.9528) (13.8284, 15.9246) (13.8134, 15.7765) knots 0.692308 0.692308 0.692308 0.692308 0.692308 0.711538 0.711538 0.711538 0.711538
  line L273 (13.7998, 16.0897) -> (13.8193, 15.9528) construction
  line L274 (13.8193, 15.9528) -> (13.8284, 15.9246) construction
  line L275 (13.8284, 15.9246) -> (13.8134, 15.7765) construction
  spline S91 degree 3 poles (13.8134, 15.7765) (13.8133, 15.7763) (13.7943, 15.5883) (13.8657, 15.6266) (13.902, 15.5249) knots 0.711538 0.711538 0.711538 0.711538 0.711538 0.730769 0.730769 0.730769 0.730769
  line L276 (13.8134, 15.7765) -> (13.7943, 15.5883) construction
  line L277 (13.7943, 15.5883) -> (13.8657, 15.6266) construction
  line L278 (13.8657, 15.6266) -> (13.902, 15.5249) construction
  spline S92 degree 3 poles (13.902, 15.5249) (13.9018, 15.525) (13.6887, 15.5945) (13.835, 15.8687) (13.7651, 16.062) knots 0.730769 0.730769 0.730769 0.730769 0.730769 0.75 0.75 0.75 0.75
  line L279 (13.902, 15.5249) -> (13.6887, 15.5945) construction
  line L280 (13.6887, 15.5945) -> (13.835, 15.8687) construction
  line L281 (13.835, 15.8687) -> (13.7651, 16.062) construction
  spline S93 degree 3 poles (13.7651, 16.062) (13.7648, 16.0621) (13.5131, 16.0901) (13.2948, 15.8728) (13.2292, 15.7053) knots 0.75 0.75 0.75 0.75 0.75 0.769231 0.769231 0.769231 0.769231
  line L282 (13.7651, 16.062) -> (13.5131, 16.0901) construction
  line L283 (13.5131, 16.0901) -> (13.2948, 15.8728) construction
  line L284 (13.2948, 15.8728) -> (13.2292, 15.7053) construction
  spline S94 degree 3 poles (13.2292, 15.7053) (13.2293, 15.7052) (13.3065, 15.6182) (13.3714, 15.6136) (13.3962, 15.5442) knots 0.769231 0.769231 0.769231 0.769231 0.769231 0.788462 0.788462 0.788462 0.788462
  line L285 (13.2292, 15.7053) -> (13.3065, 15.6182) construction
  line L286 (13.3065, 15.6182) -> (13.3714, 15.6136) construction
  line L287 (13.3714, 15.6136) -> (13.3962, 15.5442) construction
  spline S95 degree 3 poles (13.3962, 15.5442) (13.3961, 15.5442) (13.3047, 15.5747) (13.2733, 15.6348) (13.2019, 15.6746) knots 0.788462 0.788462 0.788462 0.788462 0.788462 0.807692 0.807692 0.807692 0.807692
  line L288 (13.3962, 15.5442) -> (13.3047, 15.5747) construction
  line L289 (13.3047, 15.5747) -> (13.2733, 15.6348) construction
  line L290 (13.2733, 15.6348) -> (13.2019, 15.6746) construction
  spline S96 degree 3 poles (13.2019, 15.6746) (13.2016, 15.6745) (12.8566, 15.5693) (12.5749, 15.0411) (12.6265, 14.8589) knots 0.807692 0.807692 0.807692 0.807692 0.807692 0.826923 0.826923 0.826923 0.826923
  line L291 (13.2019, 15.6746) -> (12.8566, 15.5693) construction
  line L292 (12.8566, 15.5693) -> (12.5749, 15.0411) construction
  line L293 (12.5749, 15.0411) -> (12.6265, 14.8589) construction
  spline S97 degree 3 poles (12.6265, 14.8589) (12.6266, 14.8588) (12.7641, 14.7907) (12.8827, 14.8264) (12.9909, 14.9002) knots 0.826923 0.826923 0.826923 0.826923 0.826923 0.846154 0.846154 0.846154 0.846154
  line L294 (12.6265, 14.8589) -> (12.7641, 14.7907) construction
  line L295 (12.7641, 14.7907) -> (12.8827, 14.8264) construction
  line L296 (12.8827, 14.8264) -> (12.9909, 14.9002) construction
  spline S98 degree 3 poles (12.9909, 14.9002) (12.991, 14.9002) (13.0953, 14.9713) (13.1625, 15.0095) (13.3111, 15.0415) knots 0.846154 0.846154 0.846154 0.846154 0.846154 0.865385 0.865385 0.865385 0.865385
  line L297 (12.9909, 14.9002) -> (13.0953, 14.9713) construction
  line L298 (13.0953, 14.9713) -> (13.1625, 15.0095) construction
  line L299 (13.1625, 15.0095) -> (13.3111, 15.0415) construction
  spline S99 degree 3 poles (13.3111, 15.0415) (13.3112, 15.0415) (13.4454, 15.0704) (13.5939, 15.083) (13.7344, 15.061) knots 0.865385 0.865385 0.865385 0.865385 0.865385 0.884615 0.884615 0.884615 0.884615
  line L300 (13.3111, 15.0415) -> (13.4454, 15.0704) construction
  line L301 (13.4454, 15.0704) -> (13.5939, 15.083) construction
  line L302 (13.5939, 15.083) -> (13.7344, 15.061) construction
  spline S100 degree 3 poles (13.7344, 15.061) (13.7345, 15.061) (13.8301, 15.0461) (13.9015, 15.0212) (13.982, 14.978) knots 0.884615 0.884615 0.884615 0.884615 0.884615 0.903846 0.903846 0.903846 0.903846
  line L303 (13.7344, 15.061) -> (13.8301, 15.0461) construction
  line L304 (13.8301, 15.0461) -> (13.9015, 15.0212) construction
  line L305 (13.9015, 15.0212) -> (13.982, 14.978) construction
  spline S101 degree 3 poles (13.982, 14.978) (13.9821, 14.978) (14.037, 14.9486) (14.0317, 14.9584) (14.0489, 14.9076) knots 0.903846 0.903846 0.903846 0.903846 0.903846 0.923077 0.923077 0.923077 0.923077
  line L306 (13.982, 14.978) -> (14.037, 14.9486) construction
  line L307 (14.037, 14.9486) -> (14.0317, 14.9584) construction
  line L308 (14.0317, 14.9584) -> (14.0489, 14.9076) construction
  spline S102 degree 3 poles (14.0489, 14.9076) (14.0486, 14.9077) (13.8173, 14.9963) (13.7267, 15.105) (13.2847, 15.0038) knots 0.923077 0.923077 0.923077 0.923077 0.923077 0.942308 0.942308 0.942308 0.942308
  line L309 (14.0489, 14.9076) -> (13.8173, 14.9963) construction
  line L310 (13.8173, 14.9963) -> (13.7267, 15.105) construction
  line L311 (13.7267, 15.105) -> (13.2847, 15.0038) construction
  spline S103 degree 3 poles (13.2847, 15.0038) (13.2844, 15.0037) (12.9688, 14.9314) (12.9904, 14.723) (12.597, 14.8298) knots 0.942308 0.942308 0.942308 0.942308 0.942308 0.961538 0.961538 0.961538 0.961538
  line L312 (13.2847, 15.0038) -> (12.9688, 14.9314) construction
  line L313 (12.9688, 14.9314) -> (12.9904, 14.723) construction
  line L314 (12.9904, 14.723) -> (12.597, 14.8298) construction
  spline S104 degree 3 poles (12.597, 14.8298) (12.5968, 14.8295) (12.4068, 14.5365) (12.2325, 14.073) (12.4974, 13.7521) knots 0.961538 0.961538 0.961538 0.961538 0.961538 1 1 1 1
  line L315 (12.597, 14.8298) -> (12.4068, 14.5365) construction
  line L316 (12.4068, 14.5365) -> (12.2325, 14.073) construction
  line L317 (12.2325, 14.073) -> (12.4974, 13.7521) construction
  spline S105 degree 3 poles (6.5939, 6.7607) (6.6004, 6.7443) (6.6008, 6.7563) (6.595, 6.7347) knots 0 0 0 0 0.017241 0.017241 0.017241 0.017241
  line L318 (6.5939, 6.7607) -> (6.6004, 6.7443) construction
  line L319 (6.6004, 6.7443) -> (6.6008, 6.7563) construction
  line L320 (6.6008, 6.7563) -> (6.595, 6.7347) construction
  line L321 (6.595, 6.7347) -> (6.5408, 6.6522)
  spline S106 degree 3 poles (6.5408, 6.6522) (6.5408, 6.6522) (6.5075, 6.6106) (6.4767, 6.5764) (6.4453, 6.5414) knots 0.034483 0.034483 0.034483 0.034483 0.034483 0.051724 0.051724 0.051724 0.051724
  line L322 (6.5408, 6.6522) -> (6.5075, 6.6106) construction
  line L323 (6.5075, 6.6106) -> (6.4767, 6.5764) construction
  line L324 (6.4767, 6.5764) -> (6.4453, 6.5414) construction
  spline S107 degree 3 poles (6.4453, 6.5414) (6.4452, 6.5412) (6.2848, 6.3621) (5.9566, 6.1535) (5.7294, 6.0505) knots 0.051724 0.051724 0.051724 0.051724 0.051724 0.068966 0.068966 0.068966 0.068966
  line L325 (6.4453, 6.5414) -> (6.2848, 6.3621) construction
  line L326 (6.2848, 6.3621) -> (5.9566, 6.1535) construction
  line L327 (5.9566, 6.1535) -> (5.7294, 6.0505) construction
  spline S108 degree 3 poles (5.7294, 6.0505) (5.7292, 6.0504) (5.5922, 5.9883) (5.5942, 5.9893) (5.5597, 5.8236) knots 0.068966 0.068966 0.068966 0.068966 0.068966 0.086207 0.086207 0.086207 0.086207
  line L328 (5.7294, 6.0505) -> (5.5922, 5.9883) construction
  line L329 (5.5922, 5.9883) -> (5.5942, 5.9893) construction
  line L330 (5.5942, 5.9893) -> (5.5597, 5.8236) construction
  spline S109 degree 3 poles (5.5597, 5.8236) (5.5597, 5.8235) (5.5353, 5.7066) (5.537, 5.5739) (5.5573, 5.455) knots 0.086207 0.086207 0.086207 0.086207 0.086207 0.103448 0.103448 0.103448 0.103448
  line L331 (5.5597, 5.8236) -> (5.5353, 5.7066) construction
  line L332 (5.5353, 5.7066) -> (5.537, 5.5739) construction
  line L333 (5.537, 5.5739) -> (5.5573, 5.455) construction
  spline S110 degree 3 poles (5.5573, 5.455) (5.5574, 5.4546) (5.6396, 4.973) (6.1046, 4.0836) (6.6249, 4.106) knots 0.103448 0.103448 0.103448 0.103448 0.103448 0.12069 0.12069 0.12069 0.12069
  line L334 (5.5573, 5.455) -> (5.6396, 4.973) construction
  line L335 (5.6396, 4.973) -> (6.1046, 4.0836) construction
  line L336 (6.1046, 4.0836) -> (6.6249, 4.106) construction
  spline S111 degree 3 poles (6.6249, 4.106) (6.6252, 4.1061) (6.923, 4.1189) (7.1782, 4.5233) (7.4026, 4.7423) knots 0.12069 0.12069 0.12069 0.12069 0.12069 0.137931 0.137931 0.137931 0.137931
  line L337 (6.6249, 4.106) -> (6.923, 4.1189) construction
  line L338 (6.923, 4.1189) -> (7.1782, 4.5233) construction
  line L339 (7.1782, 4.5233) -> (7.4026, 4.7423) construction
  spline S112 degree 3 poles (7.4026, 4.7423) (7.4027, 4.7424) (7.5835, 4.9188) (7.6625, 4.9252) (7.9155, 5.2297) knots 0.137931 0.137931 0.137931 0.137931 0.137931 0.155172 0.155172 0.155172 0.155172
  line L340 (7.4026, 4.7423) -> (7.5835, 4.9188) construction
  line L341 (7.5835, 4.9188) -> (7.6625, 4.9252) construction
  line L342 (7.6625, 4.9252) -> (7.9155, 5.2297) construction
  spline S113 degree 3 poles (7.9155, 5.2297) (7.9156, 5.2298) (8.023, 5.3591) (8.157, 5.5347) (8.2096, 5.7459) knots 0.155172 0.155172 0.155172 0.155172 0.155172 0.172414 0.172414 0.172414 0.172414
  line L343 (7.9155, 5.2297) -> (8.023, 5.3591) construction
  line L344 (8.023, 5.3591) -> (8.157, 5.5347) construction
  line L345 (8.157, 5.5347) -> (8.2096, 5.7459) construction
  spline S114 degree 3 poles (8.2096, 5.7459) (8.2098, 5.7466) (8.3842, 6.4471) (8.1018, 6.4949) (8.085, 6.6965) knots 0.172414 0.172414 0.172414 0.172414 0.172414 0.189655 0.189655 0.189655 0.189655
  line L346 (8.2096, 5.7459) -> (8.3842, 6.4471) construction
  line L347 (8.3842, 6.4471) -> (8.1018, 6.4949) construction
  line L348 (8.1018, 6.4949) -> (8.085, 6.6965) construction